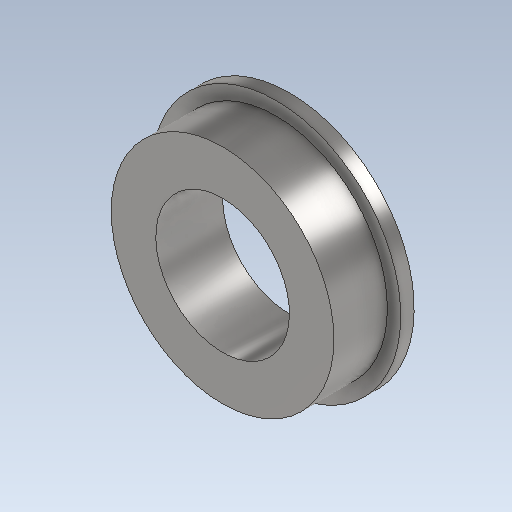
# Autodesk Inventor part: bearing_6_10_f
Saved by Autodesk Inventor 2027.1 (Build 311270010, 270A)
## iProperties
Created: 2026-10-20
Part Number: bearing_6_10_f
Material: 鋼、合金鋼
Document SubType Name: Modeling
Designer: ug_nd
Density: 7.73 g/cm^3
Appearance: 半つや出し
Author: ug_nd
Autodesk Inventor part; units mm, degrees
ref_plane "YZ Plane" through (0, 0, 0) normal (1, 0, 0) x (0, 1, 0)
ref_plane "XZ Plane" through (0, 0, 0) normal (0, 1, 0) x (-1, 0, 0)
ref_plane "XY Plane" through (0, 0, 0) normal (0, 0, 1) x (1, 0, 0)
sketch "スケッチ1" plane through (0, 0, 0) normal (1, 0, 0) x (0, 1, 0)
  line L0 (-1.12, 0) -> (6.72, 0) construction
  line L1 (0, -0.6) -> (0, 3.6) construction
  line L2 (3, 3) -> (3, 0)
  line L3 (5.6, 0) -> (3, 0)
  line L4 (5.6, 0) -> (5.6, 0.6)
  line L5 (5.6, 0.6) -> (5, 0.6)
  line L6 (5, 0.6) -> (5, 3)
  line L7 (5, 3) -> (3, 3)
  point P0 (0, 0)
  dimension "d0" = 6
  dimension "d1" = 10
  dimension "d2" = 3
  dimension "d3" = 0.6
  dimension "d4" = 11.2
  constraints: 12 end point, 3 vertical, 2 horizontal, 2 point on line
  measures "d0" diameter of L2 L1
  measures "d1" diameter of L6 L1
  measures "d2" distance between parallel lines of L0 L7
  measures "d3" distance between parallel lines of L0 L5
  measures "d4" diameter of L4 L1
revolve "回転1" add sketch "スケッチ1" angle 360 about axis through (0, 0, -10) along (0, 0, 1)
